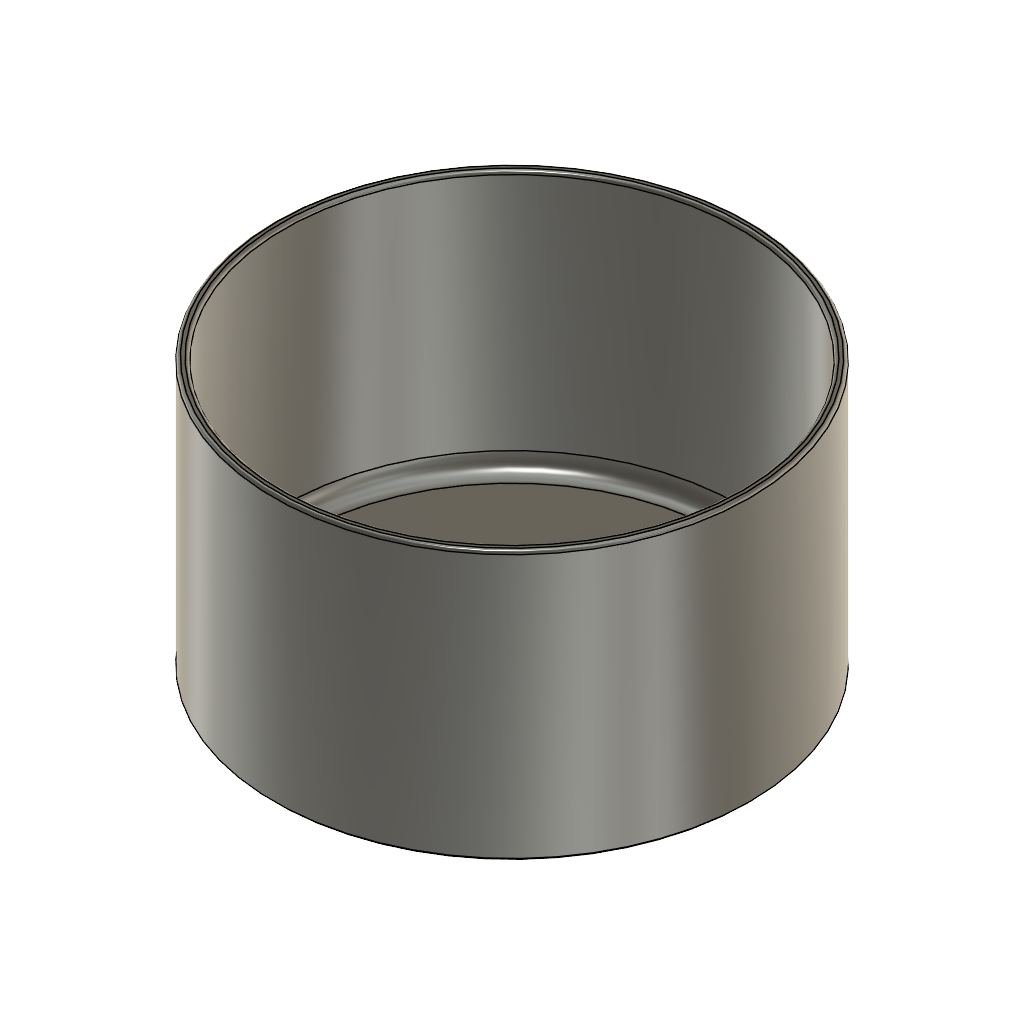
LD-S17_revB_printed_dish_115x65 (Autodesk Fusion 360 design; units mm, degrees)
part number: 2026-11-13-16-35-24-007
part number: 2026-11-13-16-35-27-827
Autodesk Fusion 360 part; units mm, degrees
sketch "Dish half-section" plane through (0, 0, 0) normal (0, 1, 0) x (1, 0, 0) in component "LD-S17_revB_printed_dish_115x65"
  line L0 (0, 0) -> (56.9, 0)
  line L1 (56.9, 0) -> (57.5, -0.6)
  line L2 (57.5, -0.6) -> (57.5, -65)
  line L3 (57.5, -65) -> (55.1, -65)
  line L4 (55.1, -65) -> (55.1, -2.4)
  line L5 (55.1, -2.4) -> (0, -2.4)
  line L6 (0, -2.4) -> (0, 0)
  dimension "d6" = 57.5
  dimension "d7" = 2.4
  dimension "d8" = 65
  dimension "d9" = 2.4
  dimension "d10" = 0.6
  dimension "d11" = 0.6
  constraint coincident L0.start L6.end
  constraint horizontal L0
  constraint horizontal L3
  constraint horizontal L5
  constraint vertical L2
  constraint vertical L4
  constraint vertical L6
  measures "d6" distance of L2 L6
  measures "d7" distance of L2 L4
  measures "d8" distance of L0 L3
  measures "d9" distance of L0 L5
  measures "d10" horizontal distance of L0.end L1.end
  measures "d11" vertical distance of L0.end L1.end
revolve "Dish revolve" add sketch "Dish half-section" angle 360 about axis through (0, 0, 2.4) along (0, 0, -1) in component "LD-S17_revB_printed_dish_115x65"
fillet "Inside floor fillet" radius 4 1 edges at (-51.3712, -19.925, 2.4) in component "LD-S17_revB_printed_dish_115x65"
fillet "Rim rounding" radius 0.8 2 edges at (-53.6088, -20.7929, 65) (-51.3712, -19.925, 65) in component "LD-S17_revB_printed_dish_115x65"
component "LD-S17_revB_printed_dish_115x65" placed x (1, 0, 0) y (0, 1, 0) z (0, 0, 1) at (0, 0, 0)
equation "dish_od = 115 mm" comment "Outside diameter; seat LD-S09 stop bore is 116.5 mm"
equation "dish_height = 65 mm" comment "Overall height = glass dish; parked cage clears the rim by 6 mm"
equation "wall_t = 2.4 mm" comment "Rev B wall: 5-6 solid perimeters with a 0.4 mm nozzle (was 0.5 mm vase mode)"
equation "floor_t = 2.4 mm" comment "Rev B floor: 12 solid layers x 0.2 mm (was 1.0 mm)"
equation "base_chamfer = 0.6 mm" comment "Outer bottom chamfer: elephant-foot relief, eases sliding into the seat"
equation "d6 = dish_od / 2"
equation "d7 = wall_t"
equation "d8 = dish_height"
equation "d9 = floor_t"
equation "d10 = base_chamfer"
equation "d11 = base_chamfer"
equation "inner_fillet_r = 4 mm" comment "Inside floor-to-wall fillet: thickens the joint where printed dishes leak, easy to wipe"
equation "rim_round_r = 0.8 mm" comment "Rounded rim edges: kind to the hose and fingers; must stay below wall_t / 2"
equation "d16 = inner_fillet_r"
equation "d18 = rim_round_r"
named bodies: "LD-S17 rev B printed dish"
